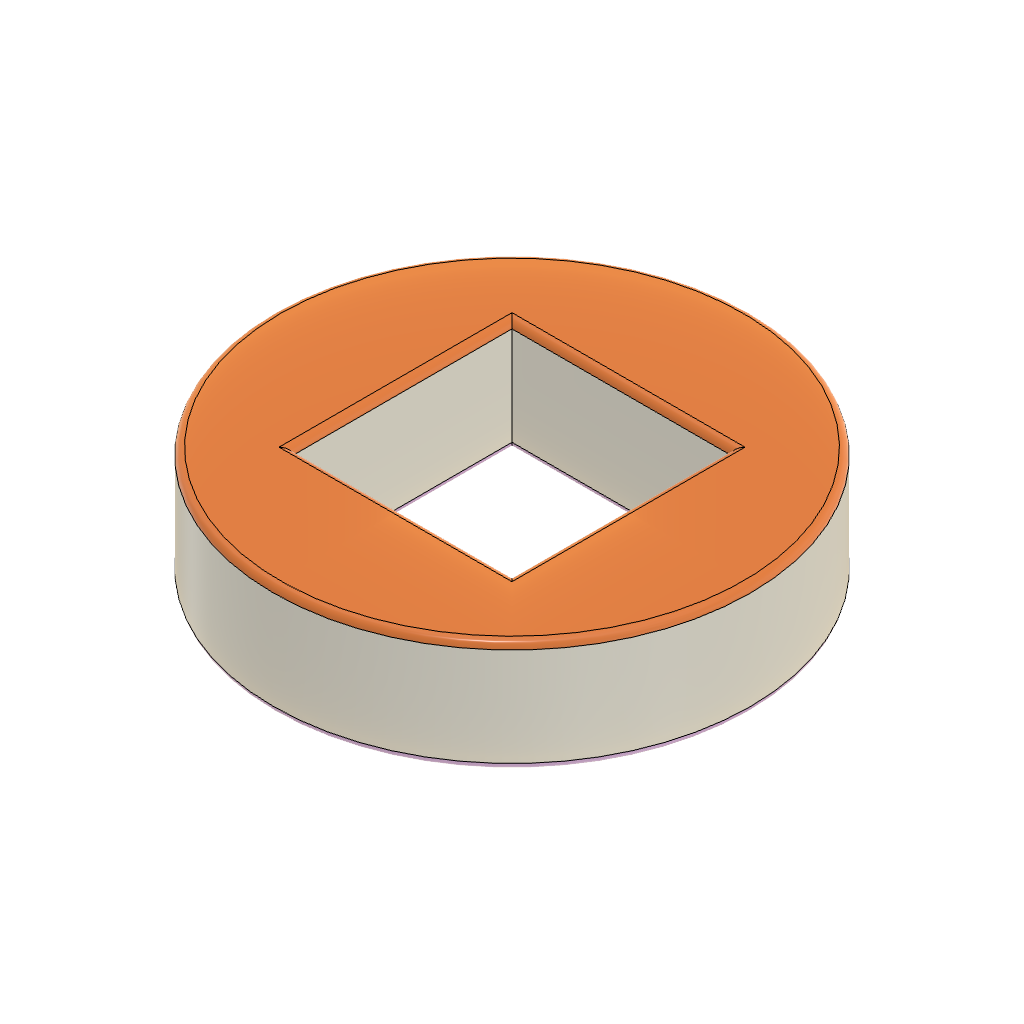
spacer_square_rod_4mm (Autodesk Fusion 360 design; units mm, degrees)
part number: 2026-10-03-17-45-10-607
Autodesk Fusion 360 part; units mm, degrees
sketch "Sketch1" plane through (0, 0, 0) normal (0, 0, 1) x (1, 0, 0)
  line L0 (3.9, 3.9) -> (-3.9, 3.9)
  line L1 (-3.9, 3.9) -> (-3.9, -3.9)
  line L2 (-3.9, -3.9) -> (3.9, -3.9)
  line L3 (3.9, -3.9) -> (3.9, 3.9)
  line L4 (3.9, 3.9) -> (-3.9, -3.9) construction
  line L5 (-3.9, 3.9) -> (3.9, -3.9) construction
  circle A0 centre (0, 0) radius 8.5
  dimension "d1" = 7.8
  dimension "d2" = 7.8
  dimension "d3" = 17
  constraint horizontal L0
  constraint perpendicular L0 L1
  constraint parallel L0 L2
  constraint parallel L1 L3
  constraint coincident L4 A0.centre
  constraint coincident L5 A0.centre
  constraint coincident A0.centre origin
  measures "d1" distance of L1.end L2.end
  measures "d2" distance of L0.end L1.end
  measures "d3" diameter of A0
extrude "Extrude1" add sketch "Sketch1" along normal blind 4
fillet "Fillet1" radius 0.25 1 edges at (-7.9248, -3.0737, 4)
fillet "Fillet2" radius 0.25 1 edges at (-7.9248, -3.0737, 0)
fillet "Fillet3" radius 0.25 4 edges at (0, 3.9, 4) (-3.9, 0, 4) (0, -3.9, 4) (3.9, 0, 4)
fillet "Fillet4" radius 0.25 4 edges at (0, 3.9, 0) (3.9, 0, 0) (0, -3.9, 0) (-3.9, 0, 0)
